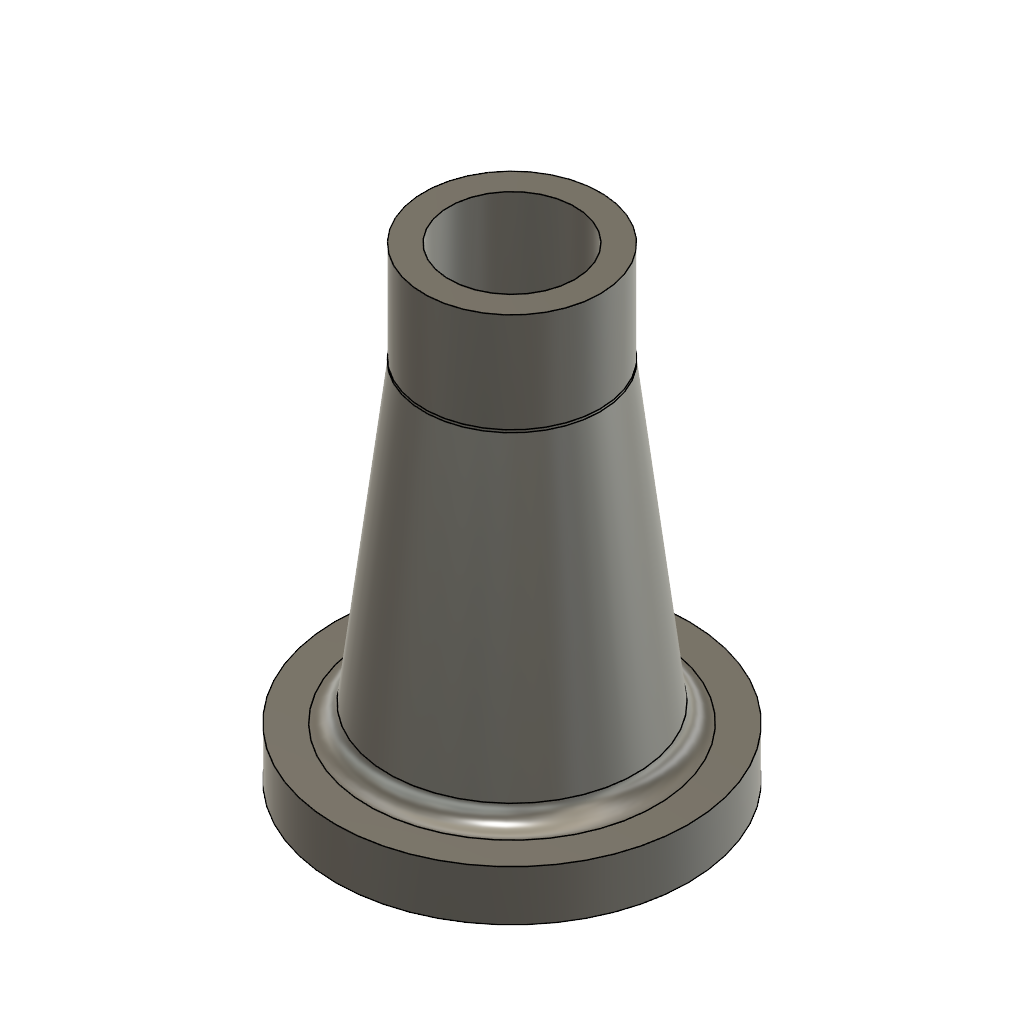
Body(screw jack) (Autodesk Fusion 360 design; units mm, degrees)
part number: 2026-11-04-17-30-23-843
Autodesk Fusion 360 part; units mm, degrees
sketch "Sketch1" plane through (0, 0, 0) normal (0, 1, 0) x (1, 0, 0)
  circle A0 centre (0, 0) radius 70
  dimension "d1" = 140
  constraint coincident A0.centre origin
  measures "d1" diameter of A0
extrude "Extrude1" add sketch "Sketch1" along normal blind 20
sketch "Sketch2" plane through (0, 20, 0) normal (0, 1, 0) x (-1, 0, 0)
  circle A0 centre (0, 0) radius 70
  circle A1 centre (0, 0) radius 50
  dimension "d4" = 100
  constraint coincident A0.centre A1.centre
  measures "d4" diameter of A1
ref_plane "WorkPlane1" through (0, 145, 0) normal (0, 1, 0) x (-1, 0, 0)
sketch "Sketch3" plane through (0, 145, 0) normal (0, 1, 0) x (1, 0, 0)
  circle A0 centre (0, 0) radius 35
  dimension "d7" = 70
  constraint coincident A0.centre origin
  measures "d7" diameter of A0
loft "Loft1" add profiles "Sketch3", "Sketch2" section 1 section 2 contours A1
fillet "Fillet1" radius 8 1 edges at (46.6164, 20, 18.0808)
sketch "Sketch4" plane through (0, 0, 0) normal (0, -1, 0) x (1, 0, 0)
  circle A0 centre (0, 0) radius 70
  circle A1 centre (0, 0) radius 40
  dimension "d10" = 80
  constraint coincident A0.centre A1.centre
  measures "d10" diameter of A1
extrude "Extrude2" cut sketch "Sketch4" against normal blind 3 contours A1
sketch "Sketch5" plane through (0, 145, 0) normal (0, 1, 0) x (-1, 0, 0)
  circle A0 centre (0, 0) radius 35
  circle A1 centre (0, 0) radius 25
  dimension "d13" = 50
  constraint coincident A0.centre A1.centre
  measures "d13" diameter of A1
loft "Loft2" cut profiles "Sketch5" section 1 contours A1 section 2 face at (9.4847, 3, -14.2223)
sketch "Sketch6" plane through (0, 145, 0) normal (0, 1, 0) x (-1, 0, 0)
  circle A0 centre (0, 0) radius 25
  circle A1 centre (0, 0) radius 35
  circle A2 centre (0, 0) radius 35
  dimension "d14" = 70
  constraint coincident A0.centre A1.centre
  measures "d14" diameter of A2
extrude "Extrude3" add sketch "Sketch6" along normal blind 40 contours A0 | A1 A2
fillet "Fillet2" radius 8 1 edges at (-32.6315, 145, -12.6565)
sketch "Sketch7" plane through (0, 185, 0) normal (0, 1, 0) x (-1, 0, 0)
  circle A0 centre (0, 0) radius 35
  circle A1 centre (0, 0) radius 25
  dimension "d19" = 50
  constraint coincident A0.centre A1.centre
  measures "d19" diameter of A1
extrude "Extrude4" cut sketch "Sketch7" against normal blind 40 contours A1
sketch "Sketch8" plane through (0, 0, 0) normal (0, -1, 0) x (1, 0, 0)
  circle A0 centre (0, 0) radius 40
  circle A1 centre (0, 0) radius 70
  circle A2 centre (0, 0) radius 50
  dimension "d22" = 100
  constraint coincident A0.centre A1.centre
  measures "d22" diameter of A2
extrude "Extrude5" cut sketch "Sketch8" against normal blind 3 contours A2
